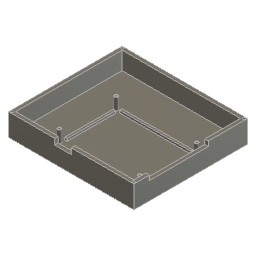
electronics housing (Autodesk Fusion 360 design; units mm, degrees)
Autodesk Fusion 360 part; units mm, degrees
sketch "Sketch1" plane through (0, 0, 0) normal (0, 1, 0) x (1, 0, 0)
  line L0 (35, 25) -> (-35, 25)
  line L1 (-35, 25) -> (-35, -25)
  line L2 (-35, -25) -> (35, -25)
  line L3 (35, -25) -> (35, 25)
  line L4 (35, 25) -> (-35, -25) construction
  line L5 (-35, 25) -> (35, -25) construction
  line L6 (50, 40) -> (-50, 40)
  line L7 (-50, 40) -> (-50, -40)
  line L8 (-50, -40) -> (50, -40)
  line L9 (50, -40) -> (50, 40)
  line L10 (50, 40) -> (-50, -40) construction
  line L11 (-50, 40) -> (50, -40) construction
  line L12 (-35, 25) -> (-34, 25)
  line L13 (-34, 25) -> (-34, 24) construction
  line L14 (-34, 24) -> (-35, 24) construction
  line L15 (-35, 24) -> (-35, 25)
  circle A0 centre (-34, 24) radius 0.5
  line L16 (35, 25) -> (34, 25)
  line L17 (34, 25) -> (34, 24) construction
  line L18 (34, 24) -> (35, 24) construction
  line L19 (35, 24) -> (35, 25)
  line L20 (35, -25) -> (34, -25) construction
  line L21 (34, -25) -> (34, -24) construction
  line L22 (34, -24) -> (35, -24) construction
  line L23 (35, -24) -> (35, -25) construction
  line L24 (-35, -25) -> (-34, -25)
  line L25 (-34, -25) -> (-34, -24) construction
  line L26 (-34, -24) -> (-35, -24) construction
  line L27 (-35, -24) -> (-35, -25)
  circle A1 centre (-34, -24) radius 0.5
  circle A2 centre (34, -24) radius 0.5
  circle A3 centre (34, 24) radius 0.5
  circle A4 centre (34, 24) radius 1.5
  circle A5 centre (-34, 24) radius 1.5
  circle A6 centre (-34, -24) radius 1.5
  circle A7 centre (34, -24) radius 1.5
  dimension "d1" = 70
  dimension "d2" = 50
  dimension "d5" = 1
  dimension "d6" = 1
  dimension "d7" = 1
  dimension "d8" = 1
  dimension "d9" = 1
  dimension "d10" = 1
  dimension "d11" = 1
  dimension "d12" = 1
  dimension "d13" = 1
  dimension "d14" = 1
  dimension "d15" = 1
  dimension "d16" = 1
  dimension "d17" = 3
  dimension "d18" = 3
  dimension "d19" = 3
  dimension "d20" = 3
  dimension "d42" = 100
  constraint horizontal L0
  constraint perpendicular L0 L1
  constraint parallel L0 L2
  constraint parallel L1 L3
  constraint coincident L4 origin
  constraint coincident L5 origin
  constraint horizontal L6
  constraint perpendicular L6 L7
  constraint parallel L6 L8
  constraint parallel L7 L9
  constraint coincident L10 origin
  constraint coincident L11 origin
  constraint horizontal L12
  constraint vertical L13
  constraint horizontal L14
  constraint vertical L15
  constraint coincident L13.end L14.start
  constraint horizontal L16
  constraint vertical L17
  constraint horizontal L18
  constraint vertical L19
  constraint horizontal L20
  constraint vertical L21
  constraint horizontal L22
  constraint vertical L23
  constraint horizontal L24
  constraint vertical L25
  constraint horizontal L26
  constraint vertical L27
  constraint coincident L25.end L26.start
  constraint coincident L21.end L22.start
  constraint coincident L17.end L18.start
  constraint concentric A3 A4
  constraint concentric A0 A5
  constraint concentric A1 A6
  constraint concentric A2 A7
  measures "d1" distance of L1.end L2.end
  measures "d2" distance of L0.end L1.end
  measures "d5" distance of L0.end L12.end
  measures "d6" distance of L0.end L14.end
  measures "d7" diameter of A0
  measures "d8" distance of L0.start L16.end
  measures "d9" distance of L0.start L18.end
  measures "d10" distance of L2.end L20.end
  measures "d11" distance of L2.end L22.end
  measures "d12" distance of L1.end L24.end
  measures "d13" distance of L1.end L26.end
  measures "d14" diameter of A1
  measures "d15" diameter of A2
  measures "d16" diameter of A3
  measures "d17" diameter of A4
  measures "d18" diameter of A5
  measures "d19" diameter of A6
  measures "d20" diameter of A7
  measures "d42" distance of L6.start L6.end
extrude "Extrude1" add sketch "Sketch1" against normal blind 4 contours L0 L3 L16 L19 A4 | L0 L3 L16 L19 A4 | L0 L1 L2 L3 A4 A5 A6 A7 | L0 L1 L12 L15 A5 | L0 L1 L12 L15 A5 | L2 L3 A7 | L2 L3 A7 | L1 L2 L24 L27 A6 | L1 L2 L24 L27 A6 | L6 L7 L8 L9 | A0 | A1 | A2 | A3
extrude "Extrude2" add sketch "Sketch1" along normal blind 12 contours L0 L3 L16 L19 A4 | L0 L3 L16 L19 A4 | L0 L1 L12 L15 A5 | L0 L1 L12 L15 A5 | L2 L3 A7 | L2 L3 A7 | L1 L2 L24 L27 A6 | L1 L2 L24 L27 A6 | A0 | A1 | A2 | A3
extrude "Extrude3" add sketch "Sketch1" along normal blind 2 contours L0 L1 L2 L3 A4 A5 A6 A7 | L6 L7 L8 L9
hole "Hole2" at (34, 12, -24) direction (0, -1, 0) diameter 2 depth 12 tip angle 118
hole "Hole3" at (-34, 12, 24) direction (0, -1, 0) diameter 2 depth 12 tip angle 118
hole "Hole4" at (-34, 12, -24) direction (0, -1, 0) diameter 2 depth 12 tip angle 118
hole "Hole5" at (34, 12, 24) direction (0, -1, 0) diameter 2 depth 12 tip angle 118
extrude "Extrude4" add 1 faces at (-16.6667, 0, -40) along direction (0, 0, -1) blind 15
extrude "Extrude5" add 1 faces at (-50, -2, 8.3333) along direction (-1, 0, 0) blind 10
extrude "Extrude6" cut 1 faces at (-23.3333, 0, 40) along direction (0, 0, -1) blind 5
move_face "OffsetFaces1" offset -10 1 faces at (50, -2, -25)
sketch "Sketch2" plane through (0, 2, 0) normal (0, 1, 0) x (-1, 0, 0)
  line L0 (60, 35) -> (-40, 35)
  line L1 (-40, 35) -> (-40, -55)
  line L2 (-40, -55) -> (60, -55)
  line L3 (60, -55) -> (60, 35)
  circle A0 centre (34, -24) radius 1.5
  circle A1 centre (-34, -24) radius 1.5
  circle A2 centre (-34, 24) radius 1.5
  circle A3 centre (34, 24) radius 1.5
  line L4 (63, 38) -> (-43, 38)
  line L5 (-43, 38) -> (-43, -58)
  line L6 (-43, -58) -> (63, -58)
  line L7 (63, -58) -> (63, 38)
  dimension "d50" = 3
extrude "Extrude7" add sketch "Sketch2" along normal blind 15 and the other way blind 6 contours L4 L5 L6 L7
move_face "OffsetFaces2" offset -2 1 faces at (-27.6667, -4, 6)
sketch "Sketch3" plane through (40, 0, 0) normal (-1, 0, 0) x (0, 0, 1)
  line L0 (-55, 2) -> (35, 2)
  line L1 (35, 2) -> (35, 17)
  line L2 (35, 17) -> (-55, 17)
  line L3 (-55, 17) -> (-55, 2)
  line L4 (-25, 13) -> (25, 13)
  line L5 (25, 13) -> (25, 25)
  line L6 (25, 25) -> (-25, 25)
  line L7 (-25, 25) -> (-25, 13)
  constraint horizontal L4
  constraint vertical L5
  constraint horizontal L6
  constraint vertical L7
extrude "Extrude8" cut sketch "Sketch3" against normal blind 20 contours L2 L5 L6 L7 | L2 L4 L5 L7
sketch "Sketch4" plane through (0, 0, 38) normal (0, 0, 1) x (1, 0, 0)
  line L0 (43, -2) -> (43, 17)
  line L1 (43, 17) -> (-63, 17)
  line L2 (-63, 17) -> (-63, -2)
  line L3 (-63, -2) -> (43, -2)
  line L4 (-32.5, 12) -> (-35.5, 12)
  line L5 (-34, 12) -> (-24, 12)
  line L6 (-24, 12) -> (-10, 12)
  line L7 (-10, 12) -> (-10, 17)
  line L8 (-10, 17) -> (-24, 17)
  line L9 (-24, 17) -> (-24, 12)
  dimension "d58" = 10
  dimension "d59" = 14
  constraint midpoint L4 L5.start
  constraint parallel L4 L5
  constraint horizontal L6
  constraint vertical L7
  constraint horizontal L8
  constraint vertical L9
  measures "d58" distance of L5.start L5.end
  measures "d59" distance of L5.end L6.end
extrude "Extrude9" cut sketch "Sketch4" against normal blind 12 contours L1 L6 L7 L8 L9
sketch "Sketch5" plane through (0, 17, 0) normal (0, 1, 0) x (-1, 0, 0)
  line L0 (24, 38) -> (24, 35)
  line L1 (24, 35) -> (60, 35)
  line L2 (60, 35) -> (60, -55)
  line L3 (60, -55) -> (-40, -55)
  line L4 (-40, -55) -> (-40, -25)
  line L5 (-40, -25) -> (-43, -25)
  line L6 (-43, -25) -> (-43, -58)
  line L7 (-43, -58) -> (63, -58)
  line L8 (63, -58) -> (63, 38)
  line L9 (63, 38) -> (24, 38)
sketch "Sketch6" plane through (0, 2, 0) normal (0, 1, 0) x (-1, 0, 0)
  line L0 (60, 35) -> (-40, 35)
  line L1 (-40, 35) -> (-40, -55)
  line L2 (-40, -55) -> (60, -55)
  line L3 (60, -55) -> (60, 35)
  circle A0 centre (34, -24) radius 1.5
  circle A1 centre (-34, -24) radius 1.5
  circle A2 centre (-34, 24) radius 1.5
  circle A3 centre (34, 24) radius 1.5
  line L4 (60, 35) -> (33.5, 35)
  line L5 (33.5, -11.5) -> (60, -11.5)
  line L6 (60, -11.5) -> (60, 35)
  line L7 (31.5, 19.954) -> (31.5, -11.5)
  line L8 (33.5, -11.5) -> (33.5, -21)
  line L9 (33.5, -21) -> (31.5, -21)
  line L10 (31.5, -11.5) -> (31.5, -21)
  line L11 (33.5, 19.954) -> (31.5, 19.954)
  line L12 (33.5, 35) -> (33.5, 22.5858)
  line L13 (33.5, 19.954) -> (33.5, -11.5)
  line L14 (36, 23) -> (60, 23)
  line L15 (60, 25) -> (36, 25)
  line L16 (36, 25) -> (36, 23)
  dimension "d62" = 26.5
  dimension "d63" = 46.5
  constraint horizontal L4
  constraint vertical L12
  constraint horizontal L5
  constraint vertical L6
  constraint coincident L0.start L3.end
  constraint perpendicular L8 L9
  constraint perpendicular L9 L10
  constraint perpendicular L7 L11
  constraint coincident A3 L12.end
  constraint collinear L12 L13
  constraint coincident L3 L14.end
  constraint coincident L6 L15.start
  constraint perpendicular L3 L15
  constraint perpendicular L14 L16
  measures "d62" distance of L0.start L4.end
  measures "d63" distance of L0.start L5.end
extrude "Extrude10" add sketch "Sketch6" along normal blind 2 contours L7 L8 L9 L10 L11 L13
extrude "Extrude11" add sketch "Sketch6" along normal blind 2 contours L3 L6 L14 L15 L16
sketch "Sketch7" plane through (0, 2, 0) normal (0, 1, 0) x (-1, 0, 0)
  line L0 (30, -25) -> (-30, -25)
  line L1 (-30, -25) -> (-30, -23)
  line L2 (-30, -23) -> (30, -23)
  line L3 (30, -23) -> (30, -25)
  dimension "d69" = 60
  dimension "d70" = 2
  constraint horizontal L0
  constraint vertical L1
  constraint horizontal L2
  constraint vertical L3
  measures "d69" distance of L0.start L0.end
  measures "d70" distance of L0.start L2.end
extrude "Extrude12" add sketch "Sketch7" along normal blind 2
sketch "Sketch8" plane through (0, 17, 0) normal (0, 1, 0) x (-1, 0, 0)
  line L0 (63, 38) -> (60, 35)
  circle A0 centre (61.5, 36.5) radius 1
  line L1 (63, -58) -> (60, -55)
  circle A1 centre (61.5, -56.5) radius 1
  line L2 (-40, -55) -> (-43, -58)
  circle A2 centre (-41.5, -56.5) radius 1
  line L3 (-40, 35) -> (-43, 38)
  circle A3 centre (-41.5, 36.5) radius 1
  dimension "d73" = 2
  dimension "d74" = 2
  dimension "d75" = 2
  dimension "d76" = 2
  constraint midpoint L0 A0.centre
  constraint midpoint L1 A1.centre
  constraint midpoint L2 A2.centre
  constraint midpoint L3 A3.centre
  measures "d73" diameter of A0
  measures "d74" diameter of A1
  measures "d75" diameter of A2
  measures "d76" diameter of A3
extrude "Extrude13" cut sketch "Sketch8" against normal blind 5
